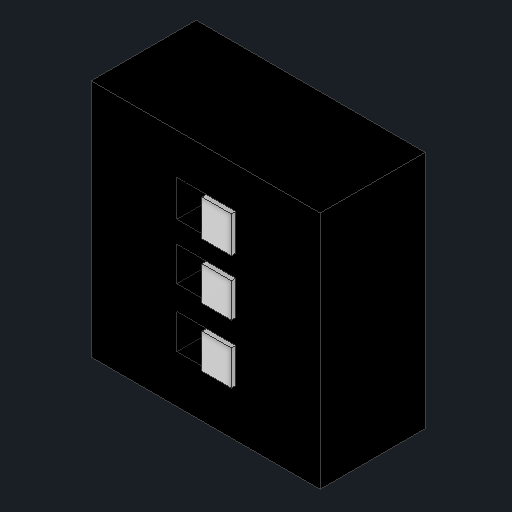
# Autodesk Inventor part: Part58
Saved by Autodesk Inventor 2027.1 (Build 311270010, 270A)
## iProperties
Created: 2024-04-23
Part Number: Part58
Material: ABS Plastic
Document SubType Name: Modeling
Designer: - LENOVO -
Density: 1.06 g/cm^3
Appearance: Smooth - White
Author: - LENOVO -
Autodesk Inventor part; units mm, degrees
ref_plane "YZ Plane" through (0, 0, 0) normal (1, 0, 0) x (0, 1, 0)
ref_plane "XZ Plane" through (0, 0, 0) normal (0, 1, 0) x (-1, 0, 0)
ref_plane "XY Plane" through (0, 0, 0) normal (0, 0, 1) x (1, 0, 0)
sketch "Sketch1" plane through (0, 0, 0) normal (0, 0, 1) x (1, 0, 0)
  line L0 (-12.6368, -5.8556) -> (-17.8674, -5.8556)
  line L1 (-17.8674, -5.8556) -> (-17.8674, -0.3924)
  line L2 (-17.8674, -0.3924) -> (-12.6368, -0.3924)
  line L3 (-12.6368, -0.3924) -> (-12.6368, -5.8556)
  line L4 (-14.5644, -1.3241) -> (-15.9075, -1.3241)
  line L5 (-15.9075, -1.3241) -> (-15.9075, -2.1506)
  line L6 (-15.9075, -2.1506) -> (-14.5644, -2.1506)
  line L7 (-14.5644, -2.1506) -> (-14.5644, -1.3241)
  line L8 (-14.5644, -2.6443) -> (-15.9075, -2.6443)
  line L9 (-15.9075, -2.6443) -> (-15.9075, -3.4249)
  line L10 (-15.9075, -3.4249) -> (-14.5644, -3.4249)
  line L11 (-14.5644, -3.4249) -> (-14.5644, -2.6443)
  line L12 (-14.5644, -3.9759) -> (-15.9075, -3.9759)
  line L13 (-15.9075, -3.9759) -> (-15.9075, -4.768)
  line L14 (-15.9075, -4.768) -> (-14.5644, -4.768)
  line L15 (-14.5644, -4.768) -> (-14.5644, -3.9759)
  point P0 (0, 0)
  constraints: 32 end point, 8 parallel, 4 horizontal, 4 perpendicular, 3 point on line, 3 vertical alignment
extrude "Extrusion1" add sketch "Sketch1" along normal blind 1.5
sketch "Sketch2" plane through (0, 0, 0) normal (0, 0, 1) x (1, 0, 0)
  line L0 (-14.5644, -1.3241) -> (-14.5644, -2.1506) projected
  line L1 (-14.5644, -2.1506) -> (-15.9075, -2.1506) projected
  line L2 (-14.5644, -1.3241) -> (-15.236, -1.3241)
  line L3 (-15.236, -1.3241) -> (-15.236, -2.1506)
  line L4 (-15.236, -2.1506) -> (-14.5644, -2.1506)
  line L5 (-14.5644, -2.1506) -> (-14.5644, -1.3241)
  line L6 (-14.5644, -2.6443) -> (-14.5644, -3.4249) projected
  line L7 (-14.5644, -3.4249) -> (-15.9075, -3.4249) projected
  line L8 (-14.5644, -2.6443) -> (-15.236, -2.6443)
  line L9 (-15.236, -2.6443) -> (-15.236, -3.4249)
  line L10 (-15.236, -3.4249) -> (-14.5644, -3.4249)
  line L11 (-14.5644, -3.4249) -> (-14.5644, -2.6443)
  line L12 (-14.5644, -3.9759) -> (-14.5644, -4.768) projected
  line L13 (-14.5644, -4.768) -> (-15.9075, -4.768) projected
  line L14 (-14.5644, -3.9759) -> (-15.236, -3.9759)
  line L15 (-15.236, -3.9759) -> (-15.236, -4.768)
  line L16 (-15.236, -4.768) -> (-14.5644, -4.768)
  line L17 (-14.5644, -4.768) -> (-14.5644, -3.9759)
  point P0 (0, 0)
  constraints: 24 end point, 6 parallel, 3 horizontal, 3 midpoint, 3 perpendicular
extrude "Extrusion2" add sketch "Sketch2" along normal blind 2.5
sketch "Sketch3" plane through (0, 0, 1.5) normal (0, 0, 1) x (1, 0, 0)
  line L0 (-15.236, -3.9759) -> (-14.5644, -3.9759) projected
  line L1 (-14.5644, -3.9759) -> (-14.5644, -4.768) projected
  line L2 (-14.5644, -4.768) -> (-15.236, -4.768) projected
  line L3 (-15.236, -4.768) -> (-15.236, -3.9759) projected
  line L4 (-15.236, -3.9759) -> (-15.9075, -3.9759) projected
  line L5 (-15.9075, -3.9759) -> (-15.9075, -4.768) projected
  line L6 (-15.9075, -4.768) -> (-15.236, -4.768) projected
  line L7 (-15.236, -1.3241) -> (-14.5644, -1.3241) projected
  line L8 (-14.5644, -1.3241) -> (-14.5644, -2.1506) projected
  line L9 (-14.5644, -2.1506) -> (-15.236, -2.1506) projected
  line L10 (-15.236, -2.1506) -> (-15.236, -1.3241) projected
  line L11 (-15.236, -1.3241) -> (-15.9075, -1.3241) projected
  line L12 (-15.9075, -1.3241) -> (-15.9075, -2.1506) projected
  line L13 (-15.9075, -2.1506) -> (-15.236, -2.1506) projected
  line L14 (-15.236, -2.6443) -> (-14.5644, -2.6443) projected
  line L15 (-14.5644, -2.6443) -> (-14.5644, -3.4249) projected
  line L16 (-14.5644, -3.4249) -> (-15.236, -3.4249) projected
  line L17 (-15.236, -3.4249) -> (-15.236, -2.6443) projected
  line L18 (-15.236, -2.6443) -> (-15.9075, -2.6443) projected
  line L19 (-15.9075, -2.6443) -> (-15.9075, -3.4249) projected
  line L20 (-15.9075, -3.4249) -> (-15.236, -3.4249) projected
  line L21 (-12.6368, -0.3924) -> (-12.6368, -5.8556) projected
  line L22 (-12.6368, -5.8556) -> (-17.8674, -5.8556) projected
  line L23 (-17.8674, -5.8556) -> (-17.8674, -0.3924) projected
  line L24 (-17.8674, -0.3924) -> (-12.6368, -0.3924) projected
  point P0 (0, 0)
extrude "Extrusion3" add sketch "Sketch3" along normal blind 0.9
body "Solid1"
